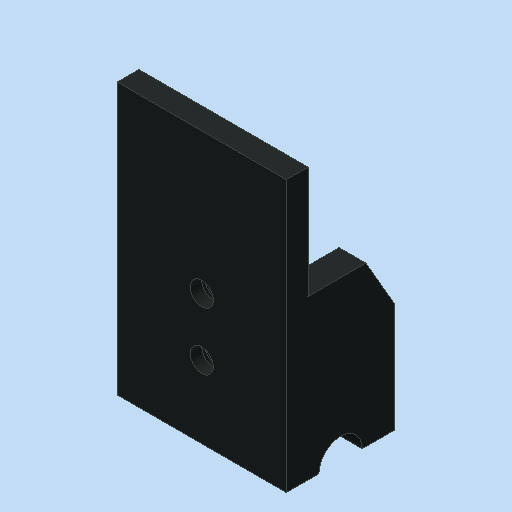
# Autodesk Inventor part: MM0868AN100_G80_508
Saved by Autodesk Inventor 2023.3 (Build 273359000, 359)
## iProperties
Part Number: MM0868AN100_G80_508
Material: Generisch
Description: =<RBPARTNOTITLE2>
Document SubType Name: Modeling
Designer: Rose
Density: 1 g/cm^3
Appearance: Grau-S
Mass: 4.30524 g
Surface Area: 32.6246 cm^2
Volume: 4.30524 cm^3
RBDOCUMENTTYPE: DRF
RBDOCUMENTVERSION: 00
RBDRAWINGMAINSCALE: 1:1
RBDRAWINGMISSINGSPEC: --
RBDRAWINGVOLUME: --
RBGBEDGESIN1: +0,5
RBGBEDGESIN2: +0,2
RBGBEDGESOUT1: -0,3
RBGBEDGESOUT2: -0,1
RBMATERIAL: --
RBMATMEETS: --
RBMATNO: =<Part Number>
RBPARTMADEOF: --
RBPARTNO: SIEHE MNR
RBPARTNOTITLE1: manufactured part
RBPARTNOTITLE2: Anfertigungsteil
RBPARTSAFETYINDICATOR: --
RBSURFACE: --
RBSURFACE2: --
RBZEDGESNORM: ISO13715:2002-06
RBZGENDIMCLASS: m
RBZGENDIMNORM: ISO 2768-1:1989-11
RBZGENGEOCLASS: H
RBZGENGEONORM: ISO 2768-2:1989-11
RBZSURFACENORM: ISO13D2:2002-02
RBZTOLERANCENORM: ISO 14405-1:2010-12
AnP_Material: =<Material>
AnP_TemplVers: 20190222
AnP_Kategorie: 1
Author: Rose
Keywords: =<RBPARTMADEOF>
Comments: =<RBSURFACE2>
Revision Number: 01
Autodesk Inventor part; units mm, degrees
ref_plane "YZ Plane" through (0, 0, 0) normal (1, 0, 0) x (0, 1, 0)
ref_plane "XZ Plane" through (0, 0, 0) normal (0, 1, 0) x (-1, 0, 0)
ref_plane "XY Plane" through (0, 0, 0) normal (0, 0, 1) x (1, 0, 0)
sketch "Skizze1" plane through (0, 0, 0) normal (0, 0, 1) x (1, 0, 0)
  line L0 (0, 18) -> (0, -3) projected
  line L1 (-16.38, 0) -> (16.38, 0) projected
  line L2 (11.7, 15) -> (11.7, 0)
  line L3 (11.7, 0) -> (-11.7, 0)
  line L4 (-11.7, 0) -> (-11.7, 15)
  line L5 (8, 15) -> (8, 3)
  line L6 (8, 3) -> (-8, 3)
  line L7 (-8, 3) -> (-8, 15)
  line L8 (-11.7, 15) -> (-8, 15)
  line L9 (8, 15) -> (11.7, 15)
  dimension "d1" = 16
  dimension "d2" = 23.4
  dimension "d4" = 3
  dimension "d7" = 15
  constraints: 16 end point, 4 parallel, 2 collinear, 2 horizontal, 2 perpendicular, 2 other
  measures "d1" distance between parallel lines of L5 L7
  measures "d2" distance between parallel lines of L2 L4
  measures "d4" distance between parallel lines of L3 L6
  measures "d7" distance between parallel lines of L1 L8
extrude "Extrusion1" add sketch "Skizze1" along normal blind 37.5
sketch "Skizze2" plane through (-11.7, 0, 0) normal (-1, 0, 0) x (0, 0, 1)
  line L0 (37.5, 3) -> (37.5, 15) projected
  line L1 (0, 3) -> (37.5, 3) projected
  line L2 (0, 15) -> (37.5, 15) projected
  line L3 (22, 3) -> (22, 11)
  line L4 (22, 11) -> (15.0718, 15)
  line L5 (0, 15) -> (0, 0) projected
  arc A0 (0, 4.5) -> (0, 10.5) centre (0, 7.5) ccw
  dimension "d8" = 15.5
  dimension "d9" = 8
  dimension "d10" = 30
  dimension "d13" = 7.5
  dimension "d14" = 3
  constraints: 4 end point, 4 point on line, 2 point on circle, 1 centre point, 1 midpoint, 1 vertical
  measures "d8" distance between parallel lines of L3 L0
  measures "d9" distance of L3.start L3.end
  measures "d10" angle of L4 L2
  measures "d13" distance of L5.end A0.centre
  measures "d14" radius of A0
extrude "Extrusion2" cut sketch "Skizze2" against normal through all contours L1 L3 L4 L2 L0 | L5 A0
sketch "Skizze3" plane through (-8, 3, 0) normal (0, 1, 0) x (1, 0, 0)
  line L0 (8, 7.5) -> (8, -45) projected
  line L1 (16, -22) -> (19.7, -22) projected
  point P0 (8, -18)
  point P1 (8, -10)
  dimension "d24" = 4
  dimension "d25" = 8
  constraints: 2 point on line
  measures "d24" distance from line of L1 point (8, -18)
  measures "d25" distance of point (8, -10) point (8, -18)
hole "Bohrung1" at (0, 3, 18) at (0, 3, 10) direction (0, -1, 0) diameter 3.2 end through all countersink diameter 6 countersink angle 90
